Motor Mount (Autodesk Fusion 360 design; units mm, degrees)
Autodesk Fusion 360 part; units mm, degrees
sketch "Sketch1" plane through (0, 0, 0) normal (0, 1, 0) x (1, 0, 0)
  arc A0 (0, 20.25) -> (0, -20.25) centre (0, 0) ccw
  arc A1 (0, 17.75) -> (0, -17.75) centre (0, 0) ccw
  line L0 (0, -17.75) -> (0, -20.25)
  line L1 (0, 20.25) -> (0, 17.75)
  line L2 (0, 20.25) -> (0, 30.25)
  line L3 (0, 30.25) -> (-0.3102, 30.25)
  line L4 (-0.3102, 30.25) -> (-3.3102, 30.25)
  line L5 (-3.3102, 30.25) -> (-3.3102, 19.9776)
  line L6 (0, -20.25) -> (0, -30.25)
  line L7 (0, -30.25) -> (-3, -30.25)
  line L8 (-3, -30.25) -> (-3, -20.0265)
  line L9 (-3, -30.25) -> (-8.5416, -18.3604)
  line L10 (-3.3102, 30.25) -> (-8.9469, 18.1663)
  dimension "d2" = 20.25
  dimension "d3" = 20.25
  dimension "d4" = 17.75
  dimension "d6" = 17.75
  dimension "d10" = 10
  dimension "d11" = 3
  dimension "d12" = 10
  dimension "d13" = 3
  constraint vertical L0
  constraint parallel L0 L1
  constraint perpendicular L2 L3
  constraint coincident A0 L5.end
  constraint perpendicular L4 L5
  constraint coincident A0 L8.end
  constraint perpendicular L7 L8
  constraint coincident A0 L9.end
  constraint coincident A0 L10.end
  measures "d2" distance of A0.centre A0.start
  measures "d3" distance of A0.centre A0.end
  measures "d4" distance of A0.centre A1.start
  measures "d6" distance of A0.centre A1.end
  measures "d10" distance of A0.start L2.end
  measures "d11" distance of L3.end L4.end
  measures "d12" distance of A0.end L6.end
  measures "d13" distance of L6.end L7.end
extrude "Extrude1" add sketch "Sketch1" along normal blind 3
extrude "Extrude2" add sketch "Sketch1" against normal blind 19 contours A0 A1 L0 L1 | A0 L2 L3 L4 L5 | A0 L6 L7 L8
sketch "Sketch2" plane through (0, -19, 0) normal (0, -1, 0) x (1, 0, 0)
  line L0 (0, -30.25) -> (0, -17.75)
  arc A0 (0, 17.75) -> (0, -17.75) centre (0, 0) ccw
  line L1 (0, 17.75) -> (0, 30.25)
  line L2 (0, 30.25) -> (-3, 30.25)
  line L3 (-3, 30.25) -> (-3, 20.0265)
  arc A1 (-3, 20.0265) -> (-3.3102, -19.9776) centre (0, 0) ccw
  line L4 (-3.3102, -19.9776) -> (-3.3102, -30.25)
  line L5 (-3.3102, -30.25) -> (0, -30.25)
  line L6 (-3, 30.25) -> (-8.5416, 18.3604)
  line L7 (-3.3102, -30.25) -> (-8.9469, -18.1663)
  point P0 (-8.5416, 18.3604)
  point P1 (-8.9469, -18.1663)
  constraint coincident L2.end L3.start
  constraint coincident P0 L6.end
  constraint coincident L4.end L5.start
  constraint coincident P1 L7.end
extrude "Extrude3" add sketch "Sketch2" along normal blind 3
sketch "Sketch3" plane through (-3.3102, 0, 0) normal (-1, 0, 0) x (0, 0, 1)
  line L0 (-19.9776, 0) -> (-30.25, 0)
  line L1 (-30.25, 0) -> (-30.25, -19)
  line L2 (-30.25, -19) -> (-19.9776, -19)
  line L3 (-19.9776, -19) -> (-19.9776, 0)
  line L4 (-21.6138, -8.25) -> (-28.6138, -8.25)
  line L5 (-28.6138, -8.25) -> (-28.6138, -1.25)
  line L6 (-28.6138, -1.25) -> (-21.6138, -1.25)
  line L7 (-21.6138, -1.25) -> (-21.6138, -8.25)
  line L8 (-21.6138, -8.25) -> (-28.6138, -1.25) construction
  line L9 (-28.6138, -8.25) -> (-21.6138, -1.25) construction
  line L10 (-21.6138, -17.75) -> (-28.6138, -17.75)
  line L11 (-28.6138, -17.75) -> (-28.6138, -10.75)
  line L12 (-28.6138, -10.75) -> (-21.6138, -10.75)
  line L13 (-21.6138, -10.75) -> (-21.6138, -17.75)
  line L14 (-21.6138, -17.75) -> (-28.6138, -10.75) construction
  line L15 (-28.6138, -17.75) -> (-21.6138, -10.75) construction
  line L16 (20.0265, 0) -> (30.25, 0)
  line L17 (30.25, -19) -> (20.0265, -19)
  line L18 (20.0265, 0) -> (20.0265, -19)
  line L19 (30.25, 0) -> (30.25, -19)
  line L20 (28.6383, -8.25) -> (21.6383, -8.25)
  line L21 (21.6383, -8.25) -> (21.6383, -1.25)
  line L22 (21.6383, -1.25) -> (28.6383, -1.25)
  line L23 (28.6383, -1.25) -> (28.6383, -8.25)
  line L24 (28.6383, -8.25) -> (21.6383, -1.25) construction
  line L25 (21.6383, -8.25) -> (28.6383, -1.25) construction
  line L26 (28.6383, -17.75) -> (21.6383, -17.75)
  line L27 (21.6383, -17.75) -> (21.6383, -10.75)
  line L28 (21.6383, -10.75) -> (28.6383, -10.75)
  line L29 (28.6383, -10.75) -> (28.6383, -17.75)
  line L30 (28.6383, -17.75) -> (21.6383, -10.75) construction
  line L31 (21.6383, -17.75) -> (28.6383, -10.75) construction
  point P0 (-25.1138, -4.75)
  point P1 (-25.1138, -14.25)
  point P2 (25.1383, -4.75)
  point P3 (25.1383, -14.25)
  dimension "d20" = 7
  dimension "d21" = 7
  dimension "d22" = 7
  dimension "d23" = 7
  dimension "d24" = 7
  dimension "d25" = 7
  dimension "d26" = 7
  dimension "d27" = 7
  constraint perpendicular L4 L5
  constraint parallel L4 L6
  constraint parallel L5 L7
  constraint horizontal L4
  constraint coincident L8 P0
  constraint coincident L9 P0
  constraint perpendicular L10 L11
  constraint parallel L10 L12
  constraint parallel L11 L13
  constraint horizontal L10
  constraint coincident L14 P1
  constraint coincident L15 P1
  constraint perpendicular L20 L21
  constraint parallel L20 L22
  constraint parallel L21 L23
  constraint horizontal L20
  constraint coincident L24 P2
  constraint coincident L25 P2
  constraint perpendicular L26 L27
  constraint parallel L26 L28
  constraint parallel L27 L29
  constraint horizontal L26
  constraint coincident L30 P3
  constraint coincident L31 P3
  measures "d20" distance of L4.end L5.end
  measures "d21" distance of L5.end L6.end
  measures "d22" distance of L11.end L12.end
  measures "d23" distance of L10.end L11.end
  measures "d24" distance of L21.end L22.end
  measures "d25" distance of L20.end L21.end
  measures "d26" distance of L26.end L27.end
  measures "d27" distance of L27.end L28.end
extrude "Extrude4" cut sketch "Sketch3" against normal blind 1.5 contours L4 L5 L6 L7 | L10 L11 L12 L13 | L20 L21 L22 L23 | L26 L27 L28 L29
sketch "Sketch4" plane through (-1.8102, 0, 0) normal (-1, 0, 0) x (0, 0, 1)
  line L0 (-21.6138, -1.25) -> (-28.6138, -1.25)
  line L1 (-28.6138, -1.25) -> (-28.6138, -8.25)
  line L2 (-28.6138, -8.25) -> (-21.6138, -8.25)
  line L3 (-21.6138, -8.25) -> (-21.6138, -1.25)
  circle A0 centre (-25.1138, -14.25) radius 2
  circle A1 centre (-25.1138, -4.75) radius 2
  circle A2 centre (25.1383, -4.75) radius 2
  circle A3 centre (25.1383, -14.25) radius 2
  point P0 (-25.1138, -14.25)
  point P1 (-25.1138, -4.75)
  point P2 (25.1383, -4.75)
  point P3 (25.1383, -14.25)
  dimension "d30" = 4
  dimension "d31" = 4
  dimension "d32" = 4
  dimension "d33" = 4
  constraint coincident P0 A0.centre
  constraint coincident P1 A1.centre
  constraint coincident P2 A2.centre
  constraint coincident P3 A3.centre
  measures "d30" diameter of A0
  measures "d31" diameter of A1
  measures "d32" diameter of A2
  measures "d33" diameter of A3
extrude "Extrude5" cut sketch "Sketch4" against normal blind 3 contours A0 | A1 | A2 | A3
